Autodesk Inventor part; units mm, degrees
(part 2 of 2)
  point P149 (0, 0)
  point P150 (-6.345, -13.6154)
  point P151 (-5.5756, -13.9498)
  point P152 (0, 0)
  point P153 (0, 0)
  point P154 (-4.7214, -14.2599)
  point P155 (-3.9185, -14.5028)
  point P156 (0, 0)
  point P157 (0, 0)
  point P158 (-3.034, -14.7116)
  point P159 (-2.2083, -14.8596)
  point P160 (0, 0)
  point P161 (0, 0)
  point P162 (-1.3056, -14.9644)
  point P163 (-0.4683, -15.0155)
  point P164 (0, 0)
  point P165 (0, 0)
  point P166 (0.4405, -15.0148)
  point P167 (1.2781, -14.9684)
  point P168 (0, 0)
  point P169 (0, 0)
  point P170 (2.1807, -14.8621)
  point P171 (3.0072, -14.7188)
  point P172 (0, 0)
  point P173 (0, 0)
  point P174 (3.8913, -14.5085)
  point P175 (4.6956, -14.2701)
  point P176 (0, 0)
  point P177 (0, 0)
  point P178 (5.5493, -13.9586)
  point P179 (6.3205, -13.6285)
  point P180 (0, 0)
  point P181 (0, 0)
  point P182 (7.1323, -13.22)
  point P183 (7.8599, -12.8026)
  point P184 (0, 0)
  point P185 (0, 0)
  point P186 (8.6188, -12.3026)
  point P187 (9.2931, -11.8036)
  point P188 (0, 0)
  point P189 (0, 0)
  point P190 (9.9888, -11.2188)
  point P191 (10.6006, -10.6449)
  point P192 (0, 0)
  point P193 (0, 0)
  point P194 (11.2237, -9.9833)
  point P195 (11.7647, -9.3423)
  point P196 (0, 0)
  point P197 (0, 0)
  point P198 (12.3068, -8.6129)
  point P199 (12.7697, -7.9133)
  dimension "d25" = 0.87
  dimension "d31" = 0.062
  dimension "d33" = 0.0585
  dimension "d45" = 1
  dimension "d47" = 5.923
  dimension "d48" = 0.9743
  dimension "d49" = 0.9708
  dimension "d50" = 0.003
  dimension "d51" = 0.0369
  dimension "d53" = 0.049
  dimension "d62" = 0.091
  dimension "d63" = 0.8134
  dimension "d84" = 14.1945
  dimension "d85" = 5.8554
  dimension "d86" = 5.0487
  dimension "d87" = 15.0174
  dimension "d88" = 15.0507
  dimension "d91" = 360
  constraints: 756 end point, 594 point on circle, 270 centre point, 56 coincident, 54 point on line, 2 collinear, 2 equal radius, 2 midpoint, 2 parallel, 1835 other
  measures "d25" distance of L0.start L1.end
  measures "d31" radius of A0
  measures "d33" vertical distance of A0.centre point (0, 0)
  measures "d45" distance between parallel lines of L1 L3
  measures "d47" radius of A1
  measures "d48" distance of L2.start L3.start
  measures "d49" distance of L3.end L2.end
  measures "d50" vertical distance of L1.end L2.end
  measures "d51" distance between parallel lines of L1 L2
  measures "d53" vertical distance of L4.end L2.end
  measures "d62" radius of A3
  measures "d63" distance of L0.start L0.end
  measures "d84" horizontal distance of point (0, 0) A1.centre
  measures "d85" vertical distance of point (0, 0) A1.centre
  measures "d86" vertical distance of point (0, 0) A2.centre
  measures "d87" horizontal distance of point (0, 0) point (15.017, 0.406)
  measures "d88" horizontal distance of point (0, 0) A3.centre
extrude "Extrusion5" add sketch "Sketch5" against normal blind 5
extrude "Extrusion6" cut sketch "Sketch2" against normal blind 2
extrude "Extrusion7" cut sketch "Sketch3" against normal blind 2.5
extrude "Extrusion8" cut sketch "Sketch4" against normal blind 0.5
body "Solid1"
